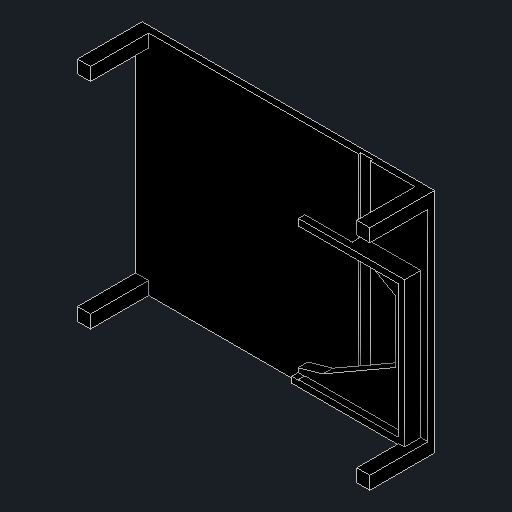
# Autodesk Inventor part: Test Sled
Saved by Autodesk Inventor 2027.2 (Build 312334000, 334)
## iProperties
Created: 2026-11-11
Part Number: Test Sled
Material: Generic
Description: Optics test jig: floor plate, board posts, module pocket, pouch slot and strip groove at the enclosure's heights
Document SubType Name: Modeling
Designer: isaac
Density: 1 g/cm^3
Appearance: Black
Author: isaac
Autodesk Inventor part; units mm, degrees
ref_plane "Work Plane1" through (0, 0, -19.9) normal (0, 0, 1) x (1, 0, 0)
sketch "Sketch1" plane through (0, 0, -19.9) normal (0, 0, 1) x (1, 0, 0)
  line L0 (0, 0) -> (90, 0)
  line L1 (90, 0) -> (90, 70)
  line L2 (90, 70) -> (0, 70)
  line L3 (0, 70) -> (0, 0)
  constraints: 8 end point, 2 parallel, 1 horizontal, 1 perpendicular
extrude "Floor plate" add sketch "Sketch1" along normal blind 2
ref_plane "Work Plane2" through (0, 0, -19.9) normal (0, 0, 1) x (1, 0, 0)
sketch "Sketch2" plane through (0, 0, -19.9) normal (0, 0, 1) x (1, 0, 0)
  line L0 (53, 3.63) -> (87.8, 3.63)
  line L1 (87.8, 3.63) -> (87.8, 48.59)
  line L2 (87.8, 48.59) -> (53, 48.59)
  line L3 (53, 48.59) -> (53, 3.63)
  constraints: 8 end point, 2 parallel, 1 horizontal, 1 perpendicular
extrude "Module block" add sketch "Sketch2" along normal blind 7
ref_plane "Work Plane3" through (0, 0, -14.9) normal (0, 0, 1) x (1, 0, 0)
sketch "Sketch3" plane through (0, 0, -14.9) normal (0, 0, 1) x (1, 0, 0)
  line L0 (55, 5.63) -> (85.8, 5.63)
  line L1 (85.8, 5.63) -> (85.8, 46.59)
  line L2 (85.8, 46.59) -> (55, 46.59)
  line L3 (55, 46.59) -> (55, 5.63)
  constraints: 8 end point, 2 parallel, 1 horizontal, 1 perpendicular
extrude "Module pocket" cut sketch "Sketch3" along normal blind 2.1
ref_plane "Work Plane4" through (0, 0, -17.9) normal (0, 0, 1) x (1, 0, 0)
sketch "Sketch4" plane through (0, 0, -17.9) normal (0, 0, 1) x (1, 0, 0)
  line L0 (83.05, 21.8165) -> (60.66, 8.9265)
  line L1 (60.66, 8.9265) -> (51, 6.1733)
  line L2 (51, 6.1733) -> (51, 56.5197)
  line L3 (51, 56.5197) -> (60.66, 53.7665)
  line L4 (60.66, 53.7665) -> (83.05, 40.8765)
  line L5 (83.05, 40.8765) -> (83.05, 21.8165)
  constraints: 12 end point
extrude "Pouch slot" cut sketch "Sketch4" along normal blind 3
ref_plane "Work Plane5" through (0, 0, -14.9) normal (0, 0, 1) x (1, 0, 0)
sketch "Sketch5" plane through (0, 0, -14.9) normal (0, 0, 1) x (1, 0, 0)
  line L0 (52.9, 5.4465) -> (55.1, 5.4465)
  line L1 (55.1, 5.4465) -> (55.1, 57.2465)
  line L2 (55.1, 57.2465) -> (52.9, 57.2465)
  line L3 (52.9, 57.2465) -> (52.9, 5.4465)
  constraints: 8 end point, 2 parallel, 1 horizontal, 1 perpendicular
extrude "Rim gap over slot" cut sketch "Sketch5" along normal blind 2.1
ref_plane "Work Plane6" through (0, 0, -18.6) normal (0, 0, 1) x (1, 0, 0)
sketch "Sketch6" plane through (0, 0, -18.6) normal (0, 0, 1) x (1, 0, 0)
  line L0 (68.6125, 10.43) -> (72.1875, 10.43)
  line L1 (72.1875, 10.43) -> (72.1875, 71)
  line L2 (72.1875, 71) -> (68.6125, 71)
  line L3 (68.6125, 71) -> (68.6125, 10.43)
  constraints: 8 end point, 2 parallel, 1 horizontal, 1 perpendicular
extrude "Strip groove" cut sketch "Sketch6" along normal blind 0.7
ref_plane "Work Plane7" through (0, 0, -17.9) normal (0, 0, 1) x (1, 0, 0)
sketch "Sketch7" plane through (0, 0, -17.9) normal (0, 0, 1) x (1, 0, 0)
  line L0 (0, 0) -> (4, 0)
  line L1 (4, 0) -> (4, 4)
  line L2 (4, 4) -> (0, 4)
  line L3 (0, 4) -> (0, 0)
  line L4 (86, 0) -> (90, 0)
  line L5 (90, 0) -> (90, 4)
  line L6 (90, 4) -> (86, 4)
  line L7 (86, 4) -> (86, 0)
  line L8 (0, 66) -> (4, 66)
  line L9 (4, 66) -> (4, 70)
  line L10 (4, 70) -> (0, 70)
  line L11 (0, 70) -> (0, 66)
  line L12 (86, 66) -> (90, 66)
  line L13 (90, 66) -> (90, 70)
  line L14 (90, 70) -> (86, 70)
  line L15 (86, 70) -> (86, 66)
  constraints: 32 end point, 8 parallel, 4 horizontal, 4 perpendicular
extrude "Board posts" add sketch "Sketch7" along normal blind 17.9
body "Solid1"
